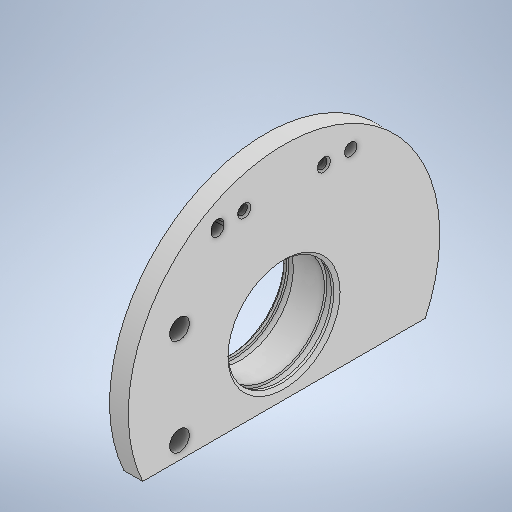
# Autodesk Inventor part: tuleja_łożyskowa_enkoder
Saved by Autodesk Inventor 2025.2 (Build 292293000, 293)
## iProperties
Created: 2025-04-07
Part Number: tuleja_łożyskowa_enkoder
Material: Ogólny
Document SubType Name: Modeling
Designer: Jan Bołtralik
Density: 1 g/cm^3
Appearance: Domyślna
Author: Jan Bołtralik
Autodesk Inventor part; units mm, degrees
ref_plane "YZ Plane" through (0, 0, 0) normal (1, 0, 0) x (0, 1, 0)
ref_plane "XZ Plane" through (0, 0, 0) normal (0, 1, 0) x (-1, 0, 0)
ref_plane "XY Plane" through (0, 0, 0) normal (0, 0, 1) x (1, 0, 0)
sketch "Szkic1" plane through (0, 0, 0) normal (0, 1, 0) x (-1, 0, 0)
  line L0 (-7.3431, 9.2974) -> (2.6569, 9.2974)
  line L1 (1.6569, 0.2974) -> (1.6569, -0.7026)
  line L2 (1.1569, -1.2026) -> (-4.3431, -1.2026)
  line L3 (-4.3431, -1.2026) -> (-4.3431, -15.7026)
  line L4 (-4.3431, -15.7026) -> (-7.3431, -15.7026)
  line L5 (-7.3431, -15.7026) -> (-7.3431, 0.2974)
  line L6 (1.6569, 0.2974) -> (1.1569, 0.7974)
  line L7 (-6.8431, 0.7974) -> (-7.3431, 0.2974)
  line L8 (1.6569, -0.7026) -> (1.1569, -1.2026)
  line L9 (1.1569, 0.7974) -> (0.7569, 0.7974)
  line L10 (0.7569, 0.7974) -> (0.7569, 0.3974)
  line L11 (0.7569, 0.3974) -> (-0.3431, 0.3974)
  line L12 (-0.3431, 0.3974) -> (-0.3431, 0.7974)
  line L13 (-6.8431, 0.7974) -> (-6.4431, 0.7974)
  line L14 (-6.4431, 0.7974) -> (-6.4431, 0.3974)
  line L15 (-6.4431, 0.3974) -> (-5.3431, 0.3974)
  line L16 (-5.3431, 0.3974) -> (-5.3431, 0.7974)
  line L17 (0.7569, 0.7974) -> (1.1569, 0.7974)
  line L18 (-6.8431, 0.7974) -> (-6.4431, 0.7974)
  line L19 (-5.3431, 0.7974) -> (-0.3431, 0.7974)
  point P0 (-7.3431, 0.7974)
  point P1 (1.6569, 0.7974)
  point P2 (1.6569, -1.2026)
  dimension "d0" = 10
  dimension "d1" = 9
  dimension "d2" = 2
  dimension "d3" = 6
  dimension "d4" = 0.5
  dimension "d5" = 0.5
  dimension "d6" = 0.5
  dimension "d7" = 0.5
  dimension "d8" = 0.5
  dimension "d9" = 0.5
  dimension "d10" = 0.4
  dimension "d11" = 0.4
  dimension "d12" = 17
  dimension "d13" = 17
  dimension "d14" = 17
  dimension "d15" = 17.8
  dimension "d16" = 1.1
  dimension "d17" = 1.1
  dimension "d18" = 50
  constraints: 40 end point, 14 perpendicular, 5 point on line, 4 horizontal, 3 parallel
  measures "d0" distance of L0.start L0.end
  measures "d1" distance of point (-7.343, 0.797) point (1.657, 0.797)
  measures "d2" distance of point (1.657, 0.797) point (1.657, -1.203)
  measures "d3" distance of point (1.657, -1.203) L2.end
  measures "d4" distance of L6.start point (1.657, 0.797)
  measures "d5" distance of L9.start point (1.657, 0.797)
  measures "d6" distance of L13.start point (-7.343, 0.797)
  measures "d7" distance of L7.end point (-7.343, 0.797)
  measures "d8" distance of L1.end point (1.657, -1.203)
  measures "d9" distance of L8.end point (1.657, -1.203)
  measures "d10" distance of L9.start L10.start
  measures "d11" distance of L13.start L14.start
  measures "d12" diameter of L17 L0
  measures "d13" diameter of L19 L0
  measures "d14" diameter of L13 L0
  measures "d15" diameter of L15 L0
  measures "d16" distance of L11.start L12.start
  measures "d17" distance of L14.end L16.start
  measures "d18" diameter of L4 L0
revolve "Obrót1" add sketch "Szkic1" angle 360 about axis through (7.3431, 0, 9.2974) along (-1, 0, 0)
sketch "Szkic2" plane through (7.3431, 0, 9.2974) normal (1, 0, 0) x (0, 0, -1)
  line L0 (-14, 23) -> (14, 23)
  line L1 (14, 23) -> (14, 16)
  line L2 (-14, 23) -> (-14, 16)
  line L3 (14, 16) -> (7, 9)
  line L4 (14, 16) -> (23.8995, 16) construction
  line L5 (-14, 16) -> (-7, 9)
  line L6 (-14, 16) -> (-4.1005, 16) construction
  line L7 (-7, 9) -> (7, 9)
  line L8 (14, 19) -> (-14, 19) construction
  line L9 (0, 23) -> (0, 9) construction
  circle A0 centre (10.7, 19) radius 1
  circle A1 centre (6.4, 19) radius 1
  circle A2 centre (-6.4, 19) radius 1
  circle A3 centre (-10.7, 19) radius 1
  line L10 (-30.1729, 25) -> (23.6773, 25)
  circle A4 centre (0, 0) radius 25 projected
  line L11 (0, 0) -> (0, 25)
  circle A5 centre (-10.7, 18.5) radius 1
  line L12 (-11.7, 19) -> (-11.7, 18.5)
  line L13 (-9.7, 19) -> (-9.7, 18.5)
  dimension "d20" = 28
  dimension "d21" = 7
  dimension "d22" = 135
  dimension "d23" = 45
  dimension "d24" = 4
  dimension "d25" = 3.3
  dimension "d26" = 7.6
  dimension "d27" = 2
  dimension "d28" = 2
  dimension "d29" = 2
  dimension "d30" = 2
  dimension "d32" = 14
  dimension "d33" = 2
  dimension "d34" = 14
  dimension "d56" = 2
  dimension "d57" = 0.5
  constraints: 28 end point, 6 horizontal, 6 point on line, 5 centre point, 4 coincident, 4 point on circle, 3 perpendicular, 2 equal length, 2 midpoint, 2 symmetric about line, 2 tangent, 1 vertical, 1 vertical alignment, 1 other
  measures "d20" distance of L0.start L0.end
  measures "d21" distance of L0.end L3.start
  measures "d22" angle of L3 L4
  measures "d23" angle of L5 L6
  measures "d24" distance between parallel lines of L0 L8
  measures "d25" distance from line of L1 point (10.7, 19)
  measures "d26" distance from line of point (6.4, 19) L1
  measures "d27" diameter of A0
  measures "d28" diameter of A1
  measures "d29" diameter of A2
  measures "d30" diameter of A3
  measures "d32" distance between parallel lines of L1 L11
  measures "d33" distance between parallel lines of L10 L0
  measures "d34" distance between parallel lines of L0 L7
  measures "d56" diameter of A5
  measures "d57" distance of A3.centre A5.centre
extrude "Wyciągnięcie proste1" cut sketch "Szkic2" against normal blind 3 contours A0 | A3 A5 | L13 A5 A3 | A3 A5 L12 | A5 A3 | A3 A5
hole "Otwór1" at (7.3431, 19, 2.8974) at (7.3431, 19, 15.6974) direction (-1, 0, 0) diameter 1.567 depth 4 tip angle 118 countersink diameter 2.1 countersink angle 90 thread size "M2x0.4" class "6H" standard "ISO Metric profile"
sketch "Szkic3" plane through (7.3431, 0, 9.2974) normal (1, 0, 0) x (0, 0, -1)
  circle A0 centre (0, 0) radius 10.5 projected
  line L0 (-38.9425, -10.5) -> (39.7759, -10.5)
  line L1 (-38.9425, -10.5) -> (-38.9425, -28.277)
  line L2 (-38.9425, -28.277) -> (39.7759, -28.277)
  line L3 (39.7759, -28.277) -> (39.7759, -10.5)
  constraints: 8 end point, 2 perpendicular, 1 horizontal, 1 tangent, 1 vertical
extrude "Wyciągnięcie proste2" cut sketch "Szkic3" against normal blind 6.25 contours L0 L3 L2 L1
sketch "Szkic5" plane through (4.3431, 0, 9.2974) normal (-1, 0, 0) x (0, 0, 1)
  line L0 (-22.6881, -10.5) -> (0, -10.5) projected
  circle A0 centre (0, 0) radius 10.5 projected
  line L1 (0, -10.5) -> (22.6881, -10.5) projected
  arc A1 (22.6881, -10.5) -> (-22.6881, -10.5) centre (0, 0) ccw projected
  circle A2 centre (6.4, 19) radius 0.7835 projected
  circle A3 centre (-6.4, 19) radius 0.7835 projected
  arc A4 (11.7, 19) -> (9.7, 19) centre (10.7, 19) ccw projected
  circle A5 centre (-10.7, 19) radius 1 projected
  line L2 (0, 0) -> (-22.6881, -10.5)
  line L3 (0, 0) -> (22.6881, -10.5)
  line L4 (0, 0) -> (-25, 0)
  line L5 (0, 0) -> (-22.6881, 10.5)
  line L6 (0, 0) -> (22.6881, 10.5)
  circle A6 centre (0, 0) radius 18.5
  line L7 (11.7, 19) -> (11.7, 18.5) projected
  arc A7 (9.7, 18.5) -> (11.7, 18.5) centre (10.7, 18.5) ccw projected
  line L8 (9.7, 18.5) -> (9.7, 19) projected
  point P0 (16.7892, 7.77)
  point P1 (16.7892, -7.77)
  dimension "d48" = 37
  constraints: 10 end point, 3 point on circle, 2 point on line, 2 symmetric about line, 1 centre point, 1 coincident, 1 horizontal, 1 vertical alignment
  measures "d48" diameter of A6
hole "Otwór2" at (4.3431, 7.77, 26.0866) at (4.3431, -7.77, 26.0866) direction (1, 0, 0) diameter 3.2 depth 8.8 clearance for "Śruba ze łbem stożkowym DIN EN ISO 2009" size "M3" standard "DIN"
equation "\"d5\" = d4"
equation "\"d6\" = d4"
equation "\"d7\" = d6"
equation "\"d8\" = d4"
equation "\"d9\" = d8"
